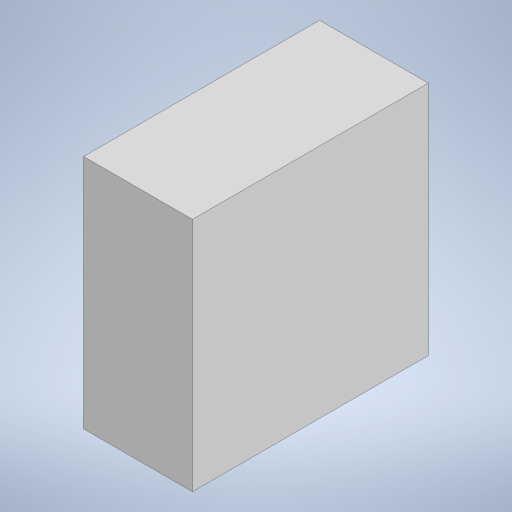
# Autodesk Inventor part: tete_arbre
Saved by Autodesk Inventor 2024 (Build 280153000, 153)
## iProperties
Created: 2025-05-15
Part Number: tete_arbre
Material: Générique
Document SubType Name: Modeling
Designer: abouabdellah
Density: 1 g/cm^3
Appearance: Par défaut
Author: abouabdellah
Autodesk Inventor part; units mm, degrees
ref_plane "YZ Plane" through (0, 0, 0) normal (1, 0, 0) x (0, 1, 0)
ref_plane "XZ Plane" through (0, 0, 0) normal (0, 1, 0) x (-1, 0, 0)
ref_plane "XY Plane" through (0, 0, 0) normal (0, 0, 1) x (1, 0, 0)
sketch "Esquisse1" plane through (0, 0, 0) normal (1, 0, 0) x (0, 1, 0)
  line L0 (19.9669, 8.0199) -> (-6.0331, 8.0199)
  line L1 (-6.0331, 8.0199) -> (-6.0331, -17.9801)
  line L2 (-6.0331, -17.9801) -> (19.9669, -17.9801)
  line L3 (19.9669, -17.9801) -> (19.9669, 8.0199)
  circle A0 centre (6.9669, -4.9801) radius 3.05
  point P0 (0, 0)
  dimension "d0" = 26
  dimension "d1" = 26
  dimension "d2" = 6.1
  constraints: 8 end point, 2 parallel, 1 centre point, 1 horizontal, 1 perpendicular
  measures "d0" distance of L2.end L1.end
  measures "d1" distance of L0.end L1.end
  measures "d2" diameter of A0
extrude "Extrusion1" add sketch "Esquisse1" along normal blind 12
sketch "Esquisse2" plane through (0, 0, 0) normal (-1, 0, 0) x (0, 0, 1)
  circle A0 centre (-4.9801, 6.9669) radius 3.05 projected
  line L0 (-6.4901, 4.3169) -> (-3.4701, 4.3169)
  circle A1 centre (-4.9801, 6.9669) radius 3.05 projected
  point P0 (0, 0)
  dimension "d5" = 0.4
  constraints: 2 end point, 1 horizontal, 1 point on circle, 2 other
extrude "Extrusion2" add sketch "Esquisse2" against normal blind 12 contours L0 A0 picked at (-5.291, 4.2323)
sketch "Esquisse4" plane through (12, 0, 0) normal (1, 0, 0) x (0, 0, -1)
  line L0 (6.4901, 4.3169) -> (3.4701, 4.3169) projected
  arc A0 (6.4901, 4.3169) -> (3.4701, 4.3169) centre (4.9801, 6.9669) ccw projected
  point P0 (0, 0)
extrude "Extrusion3" add sketch "Esquisse4" against normal blind 1
